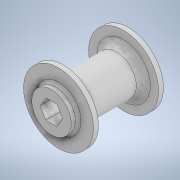
# Autodesk Inventor part: NLE_MOSOR_SFOARA_MUMIE_ULTIMA_CAMERA
Saved by Autodesk Inventor 2022.6 (Build 266554000, 554)
## iProperties
Created: 2026-11-02
Part Number: NLE_MOSOR_SFOARA_MUMIE_ULTIMA_CAMERA
Material: Generic
Document SubType Name: Modeling
Designer: Dragos Macovei
Density: 1 g/cm^3
Appearance: Default
Author: Dragos Macovei
Autodesk Inventor part; units mm, degrees
ref_plane "YZ Plane" through (0, 0, 0) normal (1, 0, 0) x (0, 1, 0)
ref_plane "XZ Plane" through (0, 0, 0) normal (0, 1, 0) x (-1, 0, 0)
ref_plane "XY Plane" through (0, 0, 0) normal (0, 0, 1) x (1, 0, 0)
sketch "Sketch1" plane through (0, 0, 0) normal (0, 1, 0) x (-1, 0, 0)
  line L0 (0, 0) -> (0, -50)
  line L1 (0, -50) -> (25, -50)
  line L2 (25, -50) -> (25, -46.5)
  line L3 (25, -46.5) -> (14.1, -46.5)
  line L4 (14.1, -46.5) -> (14.1, -3.5)
  line L5 (14.1, -3.5) -> (25, -3.5)
  line L6 (25, -3.5) -> (25, 0)
  line L7 (25, 0) -> (0, 0)
  line L8 (0, 5) -> (14.1, 5)
  line L9 (14.1, 5) -> (14.1, -3.5)
  line L10 (0, 5) -> (0, 0)
  line L11 (4.1, -50) -> (4.1, 5)
  point P0 (19.55, -3.5)
  point P1 (19.55, -46.5)
  point P2 (7.05, 5)
  point P3 (14.1, 0)
  dimension "d0" = 50
  dimension "d1" = 3.5
  dimension "d2" = 3.5
  dimension "d3" = 5
  dimension "d4" = 4.1
  dimension "d5" = 10
  dimension "d6" = 25
  dimension "d7" = 25
  constraints: 24 end point, 8 perpendicular, 3 midpoint, 3 point on line, 2 horizontal, 2 vertical
  measures "d0" distance of L0.start L0.end
  measures "d1" distance from line of point (19.55, -3.5) L7
  measures "d2" distance from line of L1 point (19.55, -46.5)
  measures "d3" distance from line of L7 point (7.05, 5)
  measures "d4" distance between parallel lines of L11 L0
  measures "d5" distance between parallel lines of L11 L4
  measures "d6" distance between parallel lines of L0 L2
  measures "d7" distance between parallel lines of L0 L6
revolve "Revolution1" add sketch "Sketch1" angle 360 about axis through (0, 0, 0) along (0, 0, -1) contours L11 L8 L9 L7 | L7 L9 L4 L3 L2 L1 L11 | L7 L6 L5 L9
sketch "Sketch2" plane through (0, 0, 5) normal (0, 0, 1) x (1, 0, 0)
  point P0 (0, 0)
sketch "Sketch3" plane through (0, 0, 5) normal (0, 0, 1) x (1, 0, 0)
  line L0 (-3.969, 6.975) -> (4.056, 6.9247)
  line L1 (4.056, 6.9247) -> (8.025, -0.0502)
  line L2 (8.025, -0.0502) -> (3.969, -6.975)
  line L3 (3.969, -6.975) -> (-4.056, -6.9247)
  line L4 (-4.056, -6.9247) -> (-8.025, 0.0502)
  line L5 (-8.025, 0.0502) -> (-3.969, 6.975)
  point P0 (0, 0)
  point P1 (0, 0)
  point P2 (5.997, -3.5126)
  dimension "d10" = 13.9
  dimension "d11" = 16.05
  constraints: 12 end point, 1 coincident, 1 midpoint, 13 other
  measures "d10" distance from line of point (5.997, -3.513) L5
  measures "d11" horizontal distance of L1.end L4.end
extrude "Extrusion1" cut sketch "Sketch3" against normal blind 45
fillet "Fillet1" radius 2 1 edges at (14.1, 0, 0)
fillet "Fillet2" radius 5 2 edges at (14.1, 0, -3.5) (14.1, 0, -46.5)
sketch "Sketch5" plane through (0, 0, -50) normal (0, 0, -1) x (-1, 0, 0)
  circle A0 centre (0, 0) radius 14.1 projected
  circle A1 centre (0, 0) radius 16.1 projected
  circle A2 centre (0, 0) radius 19.1 projected
  circle A3 centre (0, 0) radius 14.1 projected
  circle A4 centre (0, -16.1) radius 1.75
  dimension "d17" = 3.5
  constraints: 1 centre point, 1 vertical alignment, 1 other
  measures "d17" diameter of A4
extrude "Extrusion2" cut sketch "Sketch5" against normal blind 10 contours A4 A1 | A1 A4 picked at (0.0679, -15.5136) picked at (0.0558, -16.6736)
equation "\"d7\" = d6"
body "Solid1"
